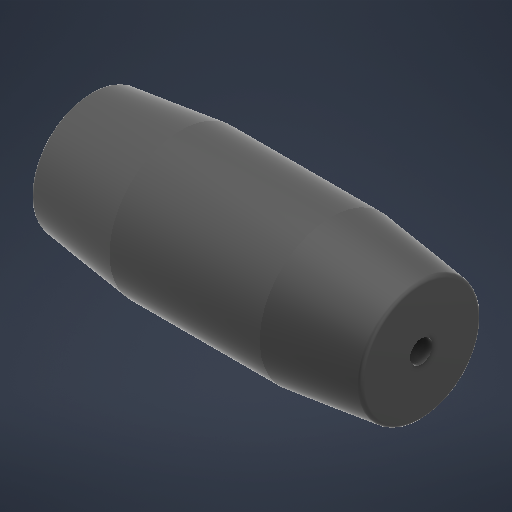
# Autodesk Inventor part: Roller mecanum
Saved by Autodesk Inventor 2026.2 (Build 302298010, 298A)
## iProperties
Created: 2026-11-18
Part Number: Roller mecanum
Material: Iron, Cast
Document SubType Name: Modeling
Designer: Administrator
Density: 7.15 g/cm^3
Appearance: Smooth - Black
Author: Administrator
Autodesk Inventor part; units mm, degrees
ref_plane "YZ Plane" through (0, 0, 0) normal (1, 0, 0) x (0, 1, 0)
ref_plane "XZ Plane" through (0, 0, 0) normal (0, 1, 0) x (-1, 0, 0)
ref_plane "XY Plane" through (0, 0, 0) normal (0, 0, 1) x (1, 0, 0)
sketch "Sketch1" plane through (0, 0, 0) normal (0, 1, 0) x (-1, 0, 0)
  line L0 (-22, 0) -> (22, 0)
  line L1 (-19, -1.5) -> (-19, -8)
  line L2 (25, -8) -> (25, -1.5)
  line L3 (25, -1.5) -> (-19, -1.5)
  line L4 (-19, -8) -> (-7.0014, -9.5)
  line L5 (-7.0014, -9.5) -> (13.0014, -9.5)
  line L6 (13.0014, -9.5) -> (25, -8)
  point P0 (0, 0)
  dimension "d0" = 44
  dimension "d1" = 16
  dimension "d3" = 3
  dimension "d6" = 19
  constraints: 14 end point, 3 equal length, 2 horizontal, 2 vertical, 1 midpoint, 1 perpendicular
  measures "d0" distance of L0.start L0.end
  measures "d1" diameter of L1.end L0
  measures "d3" diameter of L3 L0
  measures "d6" diameter of L5 L0
revolve "Revolution1" add sketch "Sketch1" angle 360 about axis through (22, 0, 0) along (-1, 0, 0)
fillet "Fillet1" radius 0.5 2 edges at (19, 0, 8) (-25, 0, 8)
body "Solid1"
